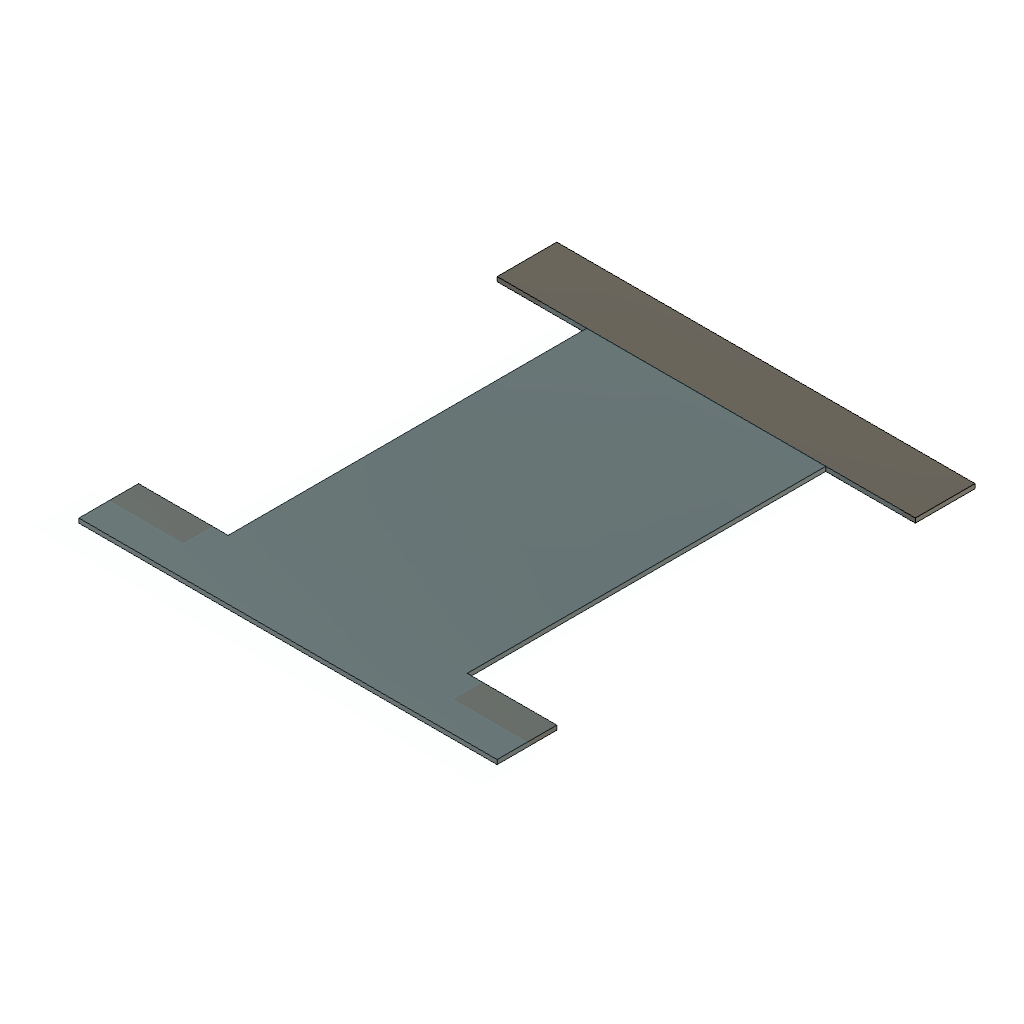
Chassis (Autodesk Fusion 360 archive; units mm, degrees)
design "Untitled"
part number: 2026-11-04-09-08-16-697
Autodesk Fusion 360 part; units mm, degrees
sketch "Sketch1" plane through (0, 0, 0) normal (0, 0, 1) x (1, 0, 0)
  line L0 (90, 130) -> (-90, 130)
  line L1 (-90, 130) -> (-90, -130)
  line L2 (-90, -130) -> (90, -130)
  line L3 (90, -130) -> (90, 130)
  line L4 (90, 130) -> (-90, -130) construction
  line L5 (-90, 130) -> (90, -130) construction
  dimension "d1" = 260
  dimension "d2" = 180
  constraint horizontal L0
  constraint perpendicular L0 L1
  constraint parallel L0 L2
  constraint parallel L1 L3
  constraint coincident L4 origin
  constraint coincident L5 origin
  measures "d1" distance of L0.end L1.end
  measures "d2" distance of L1.end L2.end
extrude "Extrude1" add sketch "Sketch1" along normal blind 3 makes body 1
sketch "Sketch2" plane through (0, 130, 0) normal (0, 1, 0) x (-1, 0, 0)
  line L0 (90, 0) -> (90, 3)
  line L1 (-90, 3) -> (-90, 0)
  line L2 (-90, 0) -> (-90, 3)
  line L3 (90, -0.0888) -> (90, 0)
  constraint vertical L2
  constraint vertical L3
  constraint coincident L1.start L2.end
  constraint coincident L0.start L3.end
sketch "Sketch3" plane through (0, 130, 0) normal (0, 1, 0) x (-1, 0, 0)
  line L0 (250, -50) -> (30, -50)
  line L1 (30, -50) -> (30, -47)
  line L2 (30, -47) -> (250, -47)
  line L3 (250, -47) -> (250, -50)
  dimension "d5" = 220
  dimension "d6" = 3
  constraint horizontal L0
  constraint vertical L1
  constraint horizontal L2
  constraint vertical L3
  measures "d5" distance of L1.end L2.end
  measures "d6" distance of L0.end L1.end
extrude "Extrude2" add sketch "Sketch3" along normal blind 20 separate body makes body 2
combine "Combine1" operation add target body 1 tool bodies 2 makes body 3 at (-176.6667, 136.6667, -50)
move_body "Move1" bodies 3 to x (1, 0, 0) y (0, 1, 0) z (0, 0, 1) at (161.0055, -0.0826, 50.4305)
extrude "Extrude3" cut 1 faces at (131.0055, 136.5841, 1.4305) along direction (-1, 0, 0) blind 40 on bodies 3 bodies 3
extrude "Extrude4" add 1 faces at (-88.9945, 136.5841, 2.4305) along direction (-1, 0, 0) blind 20 on bodies 3 bodies 1 3
extrude "Extrude5" add 1 faces at (91.0055, 136.5841, 1.4305) along direction (1, 0, 0) blind 20 on bodies 1 bodies 1
extrude "Extrude6" add 1 faces at (30.6703, 143.2783, 0.4305) along direction (0, 0, -1) blind 0.4 on bodies 1 bodies 1
extrude "Extrude7" cut 1 faces at (-35.6612, 136.5841, 3.4305) along direction (0, 0, -1) blind 0.4 on bodies 1 bodies 1
extrude "Extrude8" add 1 faces at (-108.9945, 136.5841, 2.0305) along direction (-1, 0, 0) blind 1 on bodies 1 bodies 1
extrude "Extrude9" cut 1 faces at (111.0055, 136.5841, 2.0305) along direction (-1, 0, 0) blind 1 on bodies 1 bodies 1
sketch "Sketch4" plane through (0, 0, 3) normal (0, 0, 1) x (-1, 0, 0)
  line L0 (-90, -129.9174) -> (90, -129.9174)
  line L1 (90, -129.9174) -> (90, 130)
  line L2 (90, 130) -> (-90, 130)
  line L3 (-90, 130) -> (-90, -129.9174)
  line L4 (110, 130) -> (-110, 130)
  line L5 (-110, 130) -> (-110, 150)
  line L6 (-110, 150) -> (110, 150)
  line L7 (110, 150) -> (110, 130)
  constraint horizontal L4
  constraint vertical L5
  constraint horizontal L6
  constraint vertical L7
extrude "Extrude10" add sketch "Sketch4" along normal blind 3 separate body contours L2 L4 L5 L6 L7 makes body 4
extrude "Extrude11" add 1 faces at (30, -143.3333, 3) along direction (0, 0, -1) blind 3 on bodies 4 bodies 1 4
extrude "Extrude12" cut 1 faces at (36.6667, -143.3333, 6) along direction (0, 0, -1) blind 3 on bodies 1 bodies 1
extrude "Extrude13" add 1 faces at (30.0037, 143.2783, 0.0305) along direction (0, 0, -1) blind 0.031 on bodies 1 bodies 1
sketch "Sketch5" plane through (0, 0, 3) normal (0, 0, 1) x (-1, 0, 0)
  line L0 (-110, 150) -> (-110, 130)
  line L1 (-110, 130) -> (-90, 130)
  line L2 (-90, 130) -> (-90, -129.9174)
  line L3 (-90, -129.9174) -> (90, -129.9174)
  line L4 (90, -129.9174) -> (90, 130)
  line L5 (110, 130) -> (110, 150)
  line L6 (110, 150) -> (-110, 150)
  line L7 (90, 130) -> (110, 130)
extrude "Extrude14" add 1 faces at (110.0055, 143.2507, 1.0099) along direction (1, 0, 0) blind 20 on bodies 1 bodies 1
sketch "Sketch6" plane through (130.0055, 0, 0) normal (1, 0, 0) x (0, 1, 0)
  line L0 (149.9174, 3.0305) -> (129.9174, 3.0305)
  line L1 (129.9174, 3.0305) -> (129.9174, -0.0005)
  line L2 (129.9174, -0.0005) -> (149.9174, -0.0005)
  line L3 (149.9174, -0.0005) -> (149.9174, 3.0305)
sketch "Sketch7" plane through (0, 129.9174, 0) normal (0, -1, 0) x (1, 0, 0)
  line L0 (130.0055, 3.0305) -> (-109.9945, 3.0305)
  line L1 (-109.9945, 3.0305) -> (-109.9945, -0.0005)
  line L2 (-109.9945, -0.0005) -> (-90, -0.0005)
  line L3 (-90, -0.0005) -> (-90, 0)
  line L4 (-90, 0) -> (-90, 3)
  line L5 (-90, 3) -> (90, 3)
  line L6 (90, 3) -> (90, 0)
  line L7 (90, 0) -> (90, -0.0005)
  line L8 (90, -0.0005) -> (130.0055, -0.0005)
  line L9 (130.0055, -0.0005) -> (130.0055, 3.0305)
extrude "Extrude15" add sketch "Sketch6" along normal blind 20 bodies 1
extrude "Extrude16" add 1 faces at (-23.3278, 149.9174, 2.0202) along direction (0, 1, 0) blind 20 on bodies 1 bodies 1
extrude "Extrude17" add 1 faces at (-109.9945, 156.5841, 1.0099) along direction (-1, 0, 0) blind 40 on bodies 1 bodies 1
extrude "Extrude18" add 1 faces at (36.6667, -150, 1) along direction (0, -1, 0) blind 20 on bodies 1 bodies 1
extrude "Extrude19" add 1 faces at (-110, -156.6667, 1) along direction (-1, 0, 0) blind 40 on bodies 1 bodies 1
extrude "Extrude20" add 1 faces at (110, -156.6667, 1) along direction (1, 0, 0) blind 40 on bodies 1 bodies 1
sketch "Sketch8" plane through (0, 0, 3) normal (0, 0, 1) x (-1, 0, 0)
  line L0 (-90, -129.9174) -> (90, -129.9174)
  line L1 (90, -129.9174) -> (90, 130)
  line L2 (90, 130) -> (150, 130)
  line L3 (150, 130) -> (150, 170)
  line L4 (150, 170) -> (-150, 170)
  line L5 (-150, 170) -> (-150, 130)
  line L6 (-150, 130) -> (-90, 130)
  line L7 (-90, 130) -> (-90, -129.9174)
extrude "Extrude21" cut 1 faces at (90, -43.3609, 1) along direction (-1, 0, 0) blind 10 on bodies 1 bodies 1
extrude "Extrude22" cut 1 faces at (150.0055, 143.2507, 1.0099) along direction (-1, 0, 0) blind 10 on bodies 1 bodies 1
extrude "Extrude23" cut 1 faces at (-90, 43.2783, 1) along direction (1, 0, 0) blind 10 on bodies 1 bodies 1
extrude "Extrude24" cut 1 faces at (-149.9945, 156.5841, 1.0099) along direction (1, 0, 0) blind 10 on bodies 1 bodies 1
extrude "Extrude25" cut 1 faces at (-150, -156.6667, 1) along direction (1, 0, 0) blind 10 on bodies 1 bodies 1
extrude "Extrude26" cut 1 faces at (150, -156.6667, 1) along direction (-1, 0, 0) blind 10 on bodies 1 bodies 1
extrude "Extrude27" add 2 faces at (-120, -130, 1) (100, -130, 2) along direction (0, 1, 0) blind 20 on bodies 1 bodies 1
extrude "Extrude28" cut 1 faces at (46.6667, -170, 2) along direction (0, 1, 0) blind 20 on bodies 1 bodies 1
sketch "Sketch9" plane through (0, 0, 3) normal (0, 0, 1) x (-1, 0, 0)
  line L0 (140, 150) -> (-140, 150)
  line L1 (-140, 150) -> (-140, 110)
  line L2 (-140, 110) -> (-80, 110)
  line L3 (-80, 110) -> (-80, -129.9174)
  line L4 (-80, -129.9174) -> (80, -129.9174)
  line L5 (80, -129.9174) -> (80, 110)
  line L6 (80, 110) -> (140, 110)
  line L7 (140, 110) -> (140, 150)
